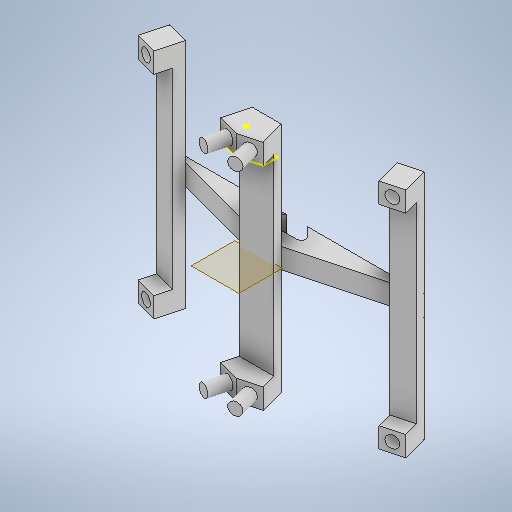
# Autodesk Inventor part: Support_tft
Saved by Autodesk Inventor 2025 (Build 290162000, 162)
## iProperties
Created: 2026-10-26
Part Number: Support_tft
Material: Generic
Document SubType Name: Modeling
Designer: diego
Density: 1 g/cm^3
Appearance: Default
Author: diego
Autodesk Inventor part; units mm, degrees
ref_plane "YZ Plane" through (0, 0, 0) normal (1, 0, 0) x (0, 1, 0)
ref_plane "XY Plane" through (0, 0, 0) normal (0, 0, 1) x (1, 0, 0)
sketch "Sketch1" plane through (0, 0, 0) normal (0, 1, 0) x (-1, 0, 0)
  line L0 (-5.216, 2.5) -> (5.216, 2.5)
  line L1 (5.216, 2.5) -> (5.216, -2.5)
  line L2 (5.216, -2.5) -> (-5.216, -2.5)
  line L3 (-5.216, -2.5) -> (-5.216, 2.5)
  line L4 (-5.216, 2.5) -> (5.216, -2.5) construction
  line L5 (5.216, 2.5) -> (-5.216, -2.5) construction
  line L6 (0, 2.5) -> (5.216, 1.1024)
  line L7 (-5.216, 1.1024) -> (5.216, 1.1024)
  line L8 (-5.216, 1.1024) -> (0, 2.5)
  point P0 (0, 0)
  dimension "d10" = 5.4
  dimension "d11" = 150
  dimension "d12" = 5
  constraints: 18 end point, 3 midpoint, 2 horizontal, 2 parallel, 2 point on line, 1 perpendicular
  measures "d10" distance of L7.start L6.start
  measures "d11" angle of L8 L6
  measures "d12" distance of L0.end L1.end
extrude "Extrusion1" add sketch "Sketch1" along normal blind 5 contours L6 L7 L8 | L7 L1 L2 L3
sketch "Sketch2" plane through (0, 5, 0) normal (0, 1, 0) x (1, 0, 0)
  point P0 (0, 0)
sketch "Sketch6" plane through (5.216, 0, 1.1024) normal (0.258819, 0, 0.9659258) x (0.9659258, 0, -0.258819)
  line L0 (-5.4, 0) -> (0, 0) projected
  line L1 (0, 0) -> (0, 5) projected
  line L2 (-5.4, 5) -> (0, 5) projected
  line L3 (-5.4, 0) -> (-5.4, 5) projected
  circle A0 centre (-2.7, 2.5) radius 1.55
  line L4 (-5.4, 5) -> (0, 0) construction
  line L5 (-5.4, 0) -> (0, 5) construction
  point P0 (-4.753, 0)
  dimension "d13" = 3.1
  constraints: 4 end point, 1 centre point, 1 coincident, 1 midpoint
  measures "d13" diameter of A0
extrude "Extrusion4" add sketch "Sketch6" along normal blind 5 contours A0
mirror "Mirror2" about plane through (0, 0, 0) normal (1, 0, 0) of "Extrusion4"
sketch "Sketch7" plane through (0, 0, 0) normal (0, -1, 0) x (1, 0, 0)
  line L0 (-5.216, -2.5) -> (-5.216, 1.1024) projected
  line L1 (5.216, -2.5) -> (-5.216, -2.5) projected
  line L2 (5.216, 1.1024) -> (5.216, -2.5) projected
  line L3 (0, 2.5) -> (5.216, 1.1024) projected
  line L4 (-5.216, 1.1024) -> (0, 2.5) projected
  point P0 (0, 0)
ref_plane "Work Plane1" through (0, -23.5, 0) normal (0, 1, 0) x (-1, 0, 0)
mirror "Mirror3" about plane through (0, -23.5, 0) normal (0, 1, 0) of "Extrusion1", "Extrusion4", "Mirror2"
sketch "Sketch8" plane through (5.216, 0, -2.5) normal (0, 0, -1) x (-1, 0, 0)
  line L0 (0, 0) -> (10.432, 0) projected
  line L1 (10.432, 0) -> (10.432, 5) projected
  line L2 (0, 5) -> (10.432, 5) projected
  line L3 (0, 0) -> (0, 5) projected
  point P0 (5.216, 0)
extrude "Extrusion6" add sketch "Sketch8" along normal blind 2.5
sketch "Sketch9" plane through (0, 0, 0) normal (0, -1, 0) x (1, 0, 0)
  line L0 (-5.216, -5) -> (-5.216, 1.1024) projected
  line L1 (5.216, -5) -> (-5.216, -5) projected
  line L2 (5.216, 1.1024) -> (5.216, -5) projected
  line L3 (0, 2.5) -> (5.216, 1.1024) projected
  line L4 (-5.216, 1.1024) -> (0, 2.5) projected
  line L5 (5.216, -2.5) -> (-5.216, -2.5) projected
  point P0 (0, 0)
extrude "Extrusion7" add sketch "Sketch9" along normal up to surface (52 mm away) contours L0 L5 L2 L1
sketch "Sketch10" plane through (-5.216, 0, 1.1024) normal (-1, 0, 0) x (0, 0, 1)
  point P0 (-1.1024, 0)
sketch "Sketch11" plane through (0, 5, 0) normal (0, 1, 0) x (1, 0, 0)
  line L0 (-5.216, -1.1024) -> (-5.216, 5) projected
  line L1 (-5.216, -1.1024) -> (0, -2.5) projected
  line L2 (0, -2.5) -> (5.216, -1.1024) projected
  line L3 (5.216, -1.1024) -> (5.216, 5) projected
  line L4 (-5.216, 5) -> (5.216, 5) projected
  line L5 (-5.216, 3.6024) -> (0, 5)
  line L6 (0, 5) -> (0, -2.5)
  line L7 (0, -2.5) -> (5.216, -1.1024) projected
  line L8 (5.216, 3.6024) -> (0, 5)
  line L9 (-5.216, 2.5) -> (-5.216, -1.1024) projected
  line L10 (-5.216, -1.1024) -> (0, 5)
  line L11 (5.216, -1.1024) -> (5.216, 5) projected
  line L12 (0, 5) -> (5.216, -1.1024)
  line L13 (-5.216, -1.1024) -> (0, 18.364)
  line L14 (5.216, -1.1024) -> (0, 18.364)
  point P0 (0, 0)
  point P1 (3.5809, 5)
  point P2 (-3.5809, 5)
  constraints: 14 end point, 2 point on line, 1 midpoint, 1 parallel, 1 perpendicular, 1 symmetric about line, 1 vertical
extrude "Extrusion8" cut sketch "Sketch11" against normal through all contours L0 L5 L13 | L5 L0 L4 L13 | L14 L8 L3 | L4 L3 L8 L14
sketch "Sketch12" plane through (-3.5809, -52, -5) normal (-0.9659258, 0, -0.258819) x (-0.258819, 0, 0.9659258)
  line L0 (6.3176, 52) -> (2.5882, 52) projected
  line L1 (6.3176, 52) -> (6.3176, 57) projected
  line L2 (0, 57) -> (6.3176, 57) projected
  line L3 (0, 0) -> (0, 57) projected
  line L4 (6.3176, 0) -> (0, 0) projected
  line L5 (6.3176, 5) -> (6.3176, 0) projected
  line L6 (2.5882, 5) -> (6.3176, 5) projected
  line L7 (2.5882, 52) -> (2.5882, 5) projected
  point P0 (3.9028, 52)
extrude "Extrusion9" add sketch "Sketch12" along normal blind 28.6
sketch "Sketch13" plane through (0, 0, 2.5) normal (-0.258819, 0, 0.9659258) x (0.9659258, 0, 0.258819)
  circle A0 centre (-2.7, 2.5) radius 1.55 projected
  line L0 (0, 0) -> (-34, 0) projected
  line L1 (0, 0) -> (0, 5) projected
  line L2 (0, 5) -> (-34, 5) projected
  line L3 (-34, 0) -> (-34, 5) projected
  circle A1 centre (-2.7, -49.5) radius 1.55 projected
  line L4 (-34, -47) -> (0, -47) projected
  line L5 (-34, -52) -> (-34, -47) projected
  line L6 (-34, -52) -> (0, -52) projected
  line L7 (0, -47) -> (0, -52) projected
  circle A2 centre (-31.3, 2.5) radius 1.5
  circle A3 centre (-31.3, -49.5) radius 1.5
  line L8 (-31.3, -49.5) -> (-2.7, -49.5)
  line L9 (-31.3, 2.5) -> (-2.7, 2.5)
  point P0 (-0.647, 0)
  dimension "d27" = 28.6
  dimension "d28" = 28.6
  dimension "d29" = 3
  constraints: 4 end point, 2 centre point, 2 horizontal, 1 equal radius
  measures "d27" distance of L9.end L9.start
  measures "d28" distance of L8.end L8.start
  measures "d29" diameter of A2
extrude "Extrusion10" cut sketch "Sketch13" against normal blind 28.6 contours A2 | A3
sketch "Sketch14" plane through (-3.5809, -52, -5) normal (0.258819, 0, -0.9659258) x (-0.9659258, 0, -0.258819)
  circle A0 centre (25.9, 2.5) radius 1.5 projected
  circle A1 centre (25.9, 54.5) radius 1.5 projected
  line L0 (0, 0) -> (0, 57) projected
  line L1 (0, 0) -> (28.6, 0) projected
  line L2 (28.6, 57) -> (28.6, 0) projected
  line L3 (0, 57) -> (28.6, 57) projected
  line L4 (0, 28.5) -> (28.6, 28.5) construction
  line L5 (23.2, 57) -> (23.2, 0)
  line L6 (0, 31) -> (23.2, 31)
  line L7 (0, 26) -> (23.2, 26)
  point P0 (-4.753, 52)
  point P1 (0, 26)
  dimension "d32" = 5.4
  dimension "d33" = 5
  constraints: 8 end point, 4 point on line, 2 midpoint, 2 perpendicular, 2 symmetric about line
  measures "d32" distance between parallel lines of L2 L5
  measures "d33" distance between parallel lines of L7 L6
extrude "Extrusion11" cut sketch "Sketch14" against normal through all contours L0 L7 L5 L1 | L0 L3 L5 L6
mirror "Mirror4" about plane through (0, 0, 0) normal (1, 0, 0) of "Extrusion9", "Extrusion10", "Extrusion11"
sketch "Sketch15" plane through (4.2507, -21, -2.5) normal (0, 1, 0) x (0.9659258, 0, -0.258819)
  line L0 (23.2, 0) -> (0, 0) projected
  line L1 (23.2, 2.5882) -> (23.2, 0) projected
  line L2 (0, 2.5882) -> (23.2, 2.5882) projected
  line L3 (0, 2.5882) -> (0, 0) projected
  line L4 (-8.2118, 2.2003) -> (-28.3036, 13.8003) projected
  line L5 (-6.9177, 4.4418) -> (-8.2118, 2.2003) projected
  line L6 (-27.0095, 16.0418) -> (-6.9177, 4.4418) projected
  line L7 (-27.0095, 16.0418) -> (-28.3036, 13.8003) projected
  line L8 (23.2, 0) -> (28.6, 0) projected
  line L9 (-30.1683, 10.5705) -> (-27.0095, 16.0418) projected
  line L10 (-27.0095, 16.0418) -> (-31.686, 18.7418) projected
  line L11 (-34.8449, 13.2705) -> (-31.686, 18.7418) projected
  line L12 (-30.1683, 10.5705) -> (-34.8449, 13.2705) projected
  line L13 (23.2, 2.5882) -> (23.2, -3.7295) projected
  line L14 (23.2, -3.7295) -> (28.6, -3.7295) projected
  line L15 (28.6, -3.7295) -> (28.6, 2.5882) projected
  line L16 (23.2, 2.5882) -> (28.6, 2.5882) projected
  line L17 (28.6, 2.5882) -> (-31.686, 18.7418)
  line L18 (0, -3.7295) -> (0, 2.5882) projected
  line L19 (-6.9177, 4.4418) -> (0, 2.5882) projected
  line L20 (-6.9177, 4.4418) -> (-10.0765, -1.0295) projected
  line L21 (-5.4, -3.7295) -> (-10.0765, -1.0295) projected
  line L22 (-5.4, -3.7295) -> (0, -3.7295) projected
  point P0 (-4.753, -1.3146)
  point P1 (-6.9177, 4.4418)
  constraints: 2 end point
extrude "Extrusion12" add sketch "Sketch15" against normal up to surface (5 mm away) contours L2 L19 L6 L10 L17 L16
sketch "Sketch16" plane through (-3.5809, -21, -5) normal (0, 1, 0) x (1, 0, 0)
  line L0 (30.2411, 3.5046) -> (7.8316, -2.5) projected
  line L1 (29.5712, 6.0046) -> (30.2411, 3.5046) projected
  line L2 (34.7872, 7.4022) -> (29.5712, 6.0046) projected
  line L3 (34.7872, 7.4022) -> (-27.6255, 7.4022) projected
  line L4 (-22.4095, 6.0046) -> (-27.6255, 7.4022) projected
  line L5 (-22.4095, 6.0046) -> (-23.0794, 3.5046) projected
  line L6 (-0.6699, -2.5) -> (-23.0794, 3.5046) projected
  line L7 (0, 0) -> (-0.6699, -2.5) projected
  line L8 (7.1617, 0) -> (0, 0) projected
  line L9 (7.1617, 0) -> (7.8316, -2.5) projected
  line L10 (8.7969, -2.5) -> (-1.6351, -2.5) projected
  line L11 (8.7969, -6.1024) -> (7.1617, 0) projected
  line L12 (0, 0) -> (7.1617, 0) projected
  line L13 (0, 0) -> (-1.6351, -6.1024) projected
  line L14 (3.5809, -7.5) -> (-1.6351, -6.1024) projected
  line L15 (3.5809, -7.5) -> (8.7969, -6.1024) projected
  line L16 (-24.0446, -0.0978) -> (-22.4095, 6.0046) projected
  line L17 (-22.4095, 6.0046) -> (-27.6255, 7.4022) projected
  line L18 (-29.2606, 1.2998) -> (-27.6255, 7.4022) projected
  line L19 (-24.0446, -0.0978) -> (-29.2606, 1.2998) projected
  line L20 (29.5712, 6.0046) -> (31.2064, -0.0978) projected
  line L21 (31.2064, -0.0978) -> (36.4224, 1.2998) projected
  line L22 (36.4224, 1.2998) -> (34.7872, 7.4022) projected
  line L23 (29.5712, 6.0046) -> (34.7872, 7.4022) projected
  line L24 (29.5712, 6.0046) -> (7.1617, 0)
  line L25 (0, 0) -> (-22.4095, 6.0046)
  point P0 (3.5809, -5)
  point P1 (-22.4095, 6.0046)
  point P2 (7.1617, 0)
  constraints: 4 end point
extrude "Extrusion13" cut sketch "Sketch16" against normal blind 10 contours L0 L9 L24 L1 | L6 L5 L25 L7
sketch "Sketch17" plane through (-31.2064, -21, -12.4022) normal (0, 1, 0) x (1, 0, 0)
  line L0 (5.216, -1.3976) -> (27.6255, -7.4022) projected
  line L1 (34.7872, -7.4022) -> (27.6255, -7.4022) projected
  line L2 (34.7872, -7.4022) -> (57.1967, -1.3976) projected
  line L3 (62.4127, 0) -> (57.1967, -1.3976) projected
  line L4 (62.4127, 0) -> (0, 0) projected
  line L5 (5.216, -1.3976) -> (0, 0) projected
  line L6 (31.2064, 0) -> (31.2064, -7.4022)
  line L7 (62.4127, 0) -> (0, 0) projected
  line L8 (33.7064, 0) -> (35.9992, -2.2929)
  line L9 (35.2921, -4) -> (31.2064, -4)
  arc A0 (35.2921, -4) -> (35.9992, -2.2929) centre (35.2921, -3) ccw
  line L10 (28.7064, 0) -> (26.4135, -2.2929)
  line L11 (27.1206, -4) -> (31.2064, -4)
  arc A1 (26.4135, -2.2929) -> (27.1206, -4) centre (27.1206, -3) ccw
  point P0 (31.2064, -12.4022)
  point P1 (28.7064, 0)
  dimension "d40" = 1
  dimension "d41" = 45
  dimension "d42" = 5
  dimension "d43" = 4
  constraints: 10 end point, 4 point on circle, 4 symmetric about line, 2 centre point, 2 midpoint, 2 point on line, 2 tangent, 1 perpendicular, 1 other
  measures "d40" radius of A0
  measures "d41" angle of L4 L8
  measures "d42" distance of L10.start L8.start
  measures "d43" distance between parallel lines of L4 L11
extrude "Extrusion14" cut sketch "Sketch17" against normal blind 10 contours L4 L6 L11 A1 L10 | L6 L4 L8 A0 L9
body "Solid1"
